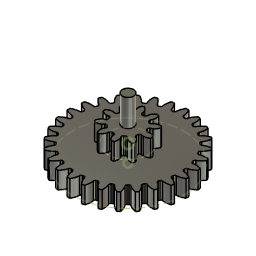
filament-respooler (Autodesk Fusion 360 archive; units mm, degrees)
design "Black Gear (new)"
description: Spur Gear; Module: 2.800000; Num Teeth: 10; Pressure Angle: 20.000000; Backlash: 0.00 mm
description: Spur Gear; Module: 2.800000; Num Teeth: 28; Pressure Angle: 20.000000; Backlash: 0.00 mm
Autodesk Fusion 360 part; units mm, degrees
(part 1 of 11)
sketch "Sketch1" plane through (0, 0, 0) normal (0, 0, 1) x (1, 0, 0) in component "Spur Gear (10 teeth)"
  circle A0 centre (0, 0) radius 10.5892
extrude "Extrude1" add sketch "Sketch1" along normal blind 12 makes body 1 in component "Spur Gear (10 teeth)"
sketch "Sketch2" plane through (0, 0, 0) normal (0, 0, 1) x (1, 0, 0) in component "Spur Gear (10 teeth)"
  spline S0 degree 5 poles (12.9616, -2.2514) (12.9724, -2.2533) (12.9939, -2.2566) (13.0264, -2.2606) (13.0698, -2.2637) (13.1245, -2.2647) (13.1793, -2.2636) (13.2343, -2.2613) (13.2894, -2.2583) (13.3446, -2.2548) (13.3998, -2.2507) (13.4551, -2.246) (13.5104, -2.2404) (13.5658, -2.2337) (13.6212, -2.226) (13.6767, -2.2173) (13.7323, -2.2079) (13.7878, -2.1977) (13.8434, -2.187) (13.899, -2.1756) (13.9546, -2.1637) (14.0101, -2.1511) (14.0657, -2.138) (14.1213, -2.1241) (14.1769, -2.1096) (14.2325, -2.0944) (14.2881, -2.0787) (14.3436, -2.0624) (14.3991, -2.0455) (14.4546, -2.0281) (14.5101, -2.0101) (14.5655, -1.9917) (14.6209, -1.9726) (14.6763, -1.953) (14.7316, -1.9329) (14.7869, -1.9123) (14.8421, -1.8911) (14.8973, -1.8695) (14.9524, -1.8473) (15.0075, -1.8247) (15.0626, -1.8015) (15.1175, -1.7779) (15.1724, -1.7538) (15.2273, -1.7292) (15.282, -1.7041) (15.3368, -1.6785) (15.3914, -1.6525) (15.446, -1.626) (15.5004, -1.5991) (15.5548, -1.5717) (15.6092, -1.5439) (15.6634, -1.5156) (15.7176, -1.4868) (15.7717, -1.4576) (15.8256, -1.428) (15.8795, -1.3979) (15.9333, -1.3674) (15.9871, -1.3365) (16.0407, -1.3051) (16.0942, -1.2733) (16.1476, -1.2411) (16.2009, -1.2085) (16.2541, -1.1755) (16.3072, -1.142) (16.3602, -1.1081) (16.413, -1.0738) (16.4658, -1.0391) (16.5184, -1.004) (16.571, -0.9685) (16.6234, -0.9327) (16.6757, -0.8964) (16.7174, -0.867) (16.7486, -0.8448) (16.7695, -0.8299) (16.7799, -0.8225) knots 0 0 0 0 0 0 0.01428571 0.02857143 0.04285714 0.05714286 0.07142857 0.08571429 0.1 0.11428571 0.12857143 0.14285714 0.15714286 0.17142857 0.18571429 0.2 0.21428571 0.22857143 0.24285714 0.25714286 0.27142857 0.28571429 0.3 0.31428571 0.32857143 0.34285714 0.35714286 0.37142857 0.38571429 0.4 0.41428571 0.42857143 0.44285714 0.45714286 0.47142857 0.48571429 0.5 0.51428571 0.52857143 0.54285714 0.55714286 0.57142857 0.58571429 0.6 0.61428571 0.62857143 0.64285714 0.65714286 0.67142857 0.68571429 0.7 0.71428571 0.72857143 0.74285714 0.75714286 0.77142857 0.78571429 0.8 0.81428571 0.82857143 0.84285714 0.85714286 0.87142857 0.88571429 0.9 0.91428571 0.92857143 0.94285714 0.95714286 0.97142857 0.98571429 1 1 1 1 1 1
  spline S1 degree 5 poles (12.9616, 2.2514) (12.9724, 2.2533) (12.9939, 2.2566) (13.0264, 2.2606) (13.0698, 2.2637) (13.1245, 2.2647) (13.1793, 2.2636) (13.2343, 2.2613) (13.2894, 2.2583) (13.3446, 2.2548) (13.3998, 2.2507) (13.4551, 2.246) (13.5104, 2.2404) (13.5658, 2.2337) (13.6212, 2.226) (13.6767, 2.2173) (13.7323, 2.2079) (13.7878, 2.1977) (13.8434, 2.187) (13.899, 2.1756) (13.9546, 2.1637) (14.0101, 2.1511) (14.0657, 2.138) (14.1213, 2.1241) (14.1769, 2.1096) (14.2325, 2.0944) (14.2881, 2.0787) (14.3436, 2.0624) (14.3991, 2.0455) (14.4546, 2.0281) (14.5101, 2.0101) (14.5655, 1.9917) (14.6209, 1.9726) (14.6763, 1.953) (14.7316, 1.9329) (14.7869, 1.9123) (14.8421, 1.8911) (14.8973, 1.8695) (14.9524, 1.8473) (15.0075, 1.8247) (15.0626, 1.8015) (15.1175, 1.7779) (15.1724, 1.7538) (15.2273, 1.7292) (15.282, 1.7041) (15.3368, 1.6785) (15.3914, 1.6525) (15.446, 1.626) (15.5004, 1.5991) (15.5548, 1.5717) (15.6092, 1.5439) (15.6634, 1.5156) (15.7176, 1.4868) (15.7717, 1.4576) (15.8256, 1.428) (15.8795, 1.3979) (15.9333, 1.3674) (15.9871, 1.3365) (16.0407, 1.3051) (16.0942, 1.2733) (16.1476, 1.2411) (16.2009, 1.2085) (16.2541, 1.1755) (16.3072, 1.142) (16.3602, 1.1081) (16.413, 1.0738) (16.4658, 1.0391) (16.5184, 1.004) (16.571, 0.9685) (16.6234, 0.9327) (16.6757, 0.8964) (16.7174, 0.867) (16.7486, 0.8448) (16.7695, 0.8299) (16.7799, 0.8225) knots 0 0 0 0 0 0 0.01428571 0.02857143 0.04285714 0.05714286 0.07142857 0.08571429 0.1 0.11428571 0.12857143 0.14285714 0.15714286 0.17142857 0.18571429 0.2 0.21428571 0.22857143 0.24285714 0.25714286 0.27142857 0.28571429 0.3 0.31428571 0.32857143 0.34285714 0.35714286 0.37142857 0.38571429 0.4 0.41428571 0.42857143 0.44285714 0.45714286 0.47142857 0.48571429 0.5 0.51428571 0.52857143 0.54285714 0.55714286 0.57142857 0.58571429 0.6 0.61428571 0.62857143 0.64285714 0.65714286 0.67142857 0.68571429 0.7 0.71428571 0.72857143 0.74285714 0.75714286 0.77142857 0.78571429 0.8 0.81428571 0.82857143 0.84285714 0.85714286 0.87142857 0.88571429 0.9 0.91428571 0.92857143 0.94285714 0.95714286 0.97142857 0.98571429 1 1 1 1 1 1
  arc A0 (16.7799, -0.8225) -> (16.7799, 0.8225) centre (0, 0) ccw
  line L0 (10.4231, -1.8122) -> (12.9616, -2.2514)
  line L1 (10.4231, 1.8122) -> (12.9616, 2.2514)
  line L2 (10.4231, -1.8122) -> (10.4231, 1.8122)
  point P0 (13.224, -2.2616)
  point P1 (13.4913, -2.2422)
  point P2 (13.7615, -2.2025)
  point P3 (14.0339, -2.1454)
  point P4 (14.3079, -2.0728)
  point P5 (14.583, -1.9856)
  point P6 (14.8588, -1.8845)
  point P7 (15.135, -1.7701)
  point P8 (15.4111, -1.6429)
  point P9 (15.6869, -1.503)
  point P10 (15.962, -1.3508)
  point P11 (16.2361, -1.1866)
  point P12 (16.5088, -1.0104)
  point P13 (13.224, 2.2616)
  point P14 (13.4913, 2.2422)
  point P15 (13.7615, 2.2025)
  point P16 (14.0339, 2.1454)
  point P17 (14.3079, 2.0728)
  point P18 (14.583, 1.9856)
  point P19 (14.8588, 1.8845)
  point P20 (15.135, 1.7701)
  point P21 (15.4111, 1.6429)
  point P22 (15.6869, 1.503)
  point P23 (15.962, 1.3508)
  point P24 (16.2361, 1.1866)
  point P25 (16.5088, 1.0104)
extrude "Extrude2" add sketch "Sketch2" along normal blind 12 bodies 1 in component "Spur Gear (10 teeth)"
fillet "Fillet1" radius 1 2 edges at (10.4327, -1.8139, 6) (10.4327, 1.8139, 6) on bodies 1 in component "Spur Gear (10 teeth)"
pattern_circular "C-Pattern1" count 10 over 360 about axis through (0, 0, 0) along (0, 0, 1) of "Extrude2", "Fillet1" in component "Spur Gear (10 teeth)"
sketch "Sketch3" plane through (0, 0, 0) normal (0, 0, 1) x (1, 0, 0) in component "Spur Gear (10 teeth)"
  circle A0 centre (0, 0) radius 14 construction
sketch "Sketch1 (2)" plane through (0, 0, 0) normal (0, 0, 1) x (1, 0, 0) in component "Spur Gear (28 teeth)"
  circle A0 centre (0, 0) radius 35.7892
extrude "Extrude1'" add sketch "Sketch1 (2)" along normal blind 12 separate body makes body 2 in component "Spur Gear (28 teeth)"
sketch "Sketch2 (2)" plane through (0, 0, 0) normal (0, 0, 1) x (1, 0, 0) in component "Spur Gear (28 teeth)"
  spline S0 degree 5 poles (36.7431, -2.6133) (36.7583, -2.6144) (36.7885, -2.6161) (36.8339, -2.6177) (36.8945, -2.6178) (36.9702, -2.615) (37.0461, -2.6101) (37.1219, -2.6041) (37.1978, -2.5973) (37.2736, -2.59) (37.3495, -2.5823) (37.4254, -2.5739) (37.5013, -2.5647) (37.5772, -2.5545) (37.6531, -2.5433) (37.7289, -2.5312) (37.8048, -2.5183) (37.8806, -2.5048) (37.9564, -2.4907) (38.0322, -2.476) (38.108, -2.4608) (38.1838, -2.4451) (38.2595, -2.4287) (38.3352, -2.4118) (38.4109, -2.3942) (38.4865, -2.3761) (38.5621, -2.3574) (38.6377, -2.3382) (38.7132, -2.3184) (38.7887, -2.2982) (38.8642, -2.2775) (38.9396, -2.2563) (39.015, -2.2346) (39.0904, -2.2125) (39.1657, -2.1898) (39.2409, -2.1667) (39.3162, -2.1431) (39.3913, -2.1191) (39.4665, -2.0946) (39.5415, -2.0697) (39.6166, -2.0443) (39.6916, -2.0185) (39.7665, -1.9923) (39.8414, -1.9656) (39.9162, -1.9385) (39.991, -1.911) (40.0658, -1.8831) (40.1405, -1.8548) (40.2151, -1.8261) (40.2896, -1.797) (40.3642, -1.7675) (40.4386, -1.7375) (40.513, -1.7072) (40.5874, -1.6765) (40.6616, -1.6455) (40.7359, -1.614) (40.81, -1.5822) (40.8841, -1.55) (40.9581, -1.5174) (41.0321, -1.4844) (41.106, -1.4511) (41.1798, -1.4174) (41.2536, -1.3834) (41.3273, -1.349) (41.401, -1.3142) (41.4745, -1.2791) (41.548, -1.2436) (41.6215, -1.2078) (41.6948, -1.1716) (41.7681, -1.1351) (41.8413, -1.0982) (41.8998, -1.0684) (41.9437, -1.0459) (41.9729, -1.0309) (41.9875, -1.0233) knots 0 0 0 0 0 0 0.01428571 0.02857143 0.04285714 0.05714286 0.07142857 0.08571429 0.1 0.11428571 0.12857143 0.14285714 0.15714286 0.17142857 0.18571429 0.2 0.21428571 0.22857143 0.24285714 0.25714286 0.27142857 0.28571429 0.3 0.31428571 0.32857143 0.34285714 0.35714286 0.37142857 0.38571429 0.4 0.41428571 0.42857143 0.44285714 0.45714286 0.47142857 0.48571429 0.5 0.51428571 0.52857143 0.54285714 0.55714286 0.57142857 0.58571429 0.6 0.61428571 0.62857143 0.64285714 0.65714286 0.67142857 0.68571429 0.7 0.71428571 0.72857143 0.74285714 0.75714286 0.77142857 0.78571429 0.8 0.81428571 0.82857143 0.84285714 0.85714286 0.87142857 0.88571429 0.9 0.91428571 0.92857143 0.94285714 0.95714286 0.97142857 0.98571429 1 1 1 1 1 1
  spline S1 degree 5 poles (36.7431, 2.6133) (36.7583, 2.6144) (36.7885, 2.6161) (36.8339, 2.6177) (36.8945, 2.6178) (36.9702, 2.615) (37.0461, 2.6101) (37.1219, 2.6041) (37.1978, 2.5973) (37.2736, 2.59) (37.3495, 2.5823) (37.4254, 2.5739) (37.5013, 2.5647) (37.5772, 2.5545) (37.6531, 2.5433) (37.7289, 2.5312) (37.8048, 2.5183) (37.8806, 2.5048) (37.9564, 2.4907) (38.0322, 2.476) (38.108, 2.4608) (38.1838, 2.4451) (38.2595, 2.4287) (38.3352, 2.4118) (38.4109, 2.3942) (38.4865, 2.3761) (38.5621, 2.3574) (38.6377, 2.3382) (38.7132, 2.3184) (38.7887, 2.2982) (38.8642, 2.2775) (38.9396, 2.2563) (39.015, 2.2346) (39.0904, 2.2125) (39.1657, 2.1898) (39.2409, 2.1667) (39.3162, 2.1431) (39.3913, 2.1191) (39.4665, 2.0946) (39.5415, 2.0697) (39.6166, 2.0443) (39.6916, 2.0185) (39.7665, 1.9923) (39.8414, 1.9656) (39.9162, 1.9385) (39.991, 1.911) (40.0658, 1.8831) (40.1405, 1.8548) (40.2151, 1.8261) (40.2896, 1.797) (40.3642, 1.7675) (40.4386, 1.7375) (40.513, 1.7072) (40.5874, 1.6765) (40.6616, 1.6455) (40.7359, 1.614) (40.81, 1.5822) (40.8841, 1.55) (40.9581, 1.5174) (41.0321, 1.4844) (41.106, 1.4511) (41.1798, 1.4174) (41.2536, 1.3834) (41.3273, 1.349) (41.401, 1.3142) (41.4745, 1.2791) (41.548, 1.2436) (41.6215, 1.2078) (41.6948, 1.1716) (41.7681, 1.1351) (41.8413, 1.0982) (41.8998, 1.0684) (41.9437, 1.0459) (41.9729, 1.0309) (41.9875, 1.0233) knots 0 0 0 0 0 0 0.01428571 0.02857143 0.04285714 0.05714286 0.07142857 0.08571429 0.1 0.11428571 0.12857143 0.14285714 0.15714286 0.17142857 0.18571429 0.2 0.21428571 0.22857143 0.24285714 0.25714286 0.27142857 0.28571429 0.3 0.31428571 0.32857143 0.34285714 0.35714286 0.37142857 0.38571429 0.4 0.41428571 0.42857143 0.44285714 0.45714286 0.47142857 0.48571429 0.5 0.51428571 0.52857143 0.54285714 0.55714286 0.57142857 0.58571429 0.6 0.61428571 0.62857143 0.64285714 0.65714286 0.67142857 0.68571429 0.7 0.71428571 0.72857143 0.74285714 0.75714286 0.77142857 0.78571429 0.8 0.81428571 0.82857143 0.84285714 0.85714286 0.87142857 0.88571429 0.9 0.91428571 0.92857143 0.94285714 0.95714286 0.97142857 0.98571429 1 1 1 1 1 1
  arc A0 (41.9875, -1.0233) -> (41.9875, 1.0233) centre (0, 0) ccw
  line L0 (35.689, -2.5391) -> (36.7431, -2.6133)
  line L1 (35.689, 2.5391) -> (36.7431, 2.6133)
  line L2 (35.689, -2.5391) -> (35.689, 2.5391)
  point P0 (37.1135, -2.6046)
  point P1 (37.4859, -2.5664)
  point P2 (37.8595, -2.5085)
  point P3 (38.234, -2.4342)
  point P4 (38.6091, -2.3454)
  point P5 (38.9846, -2.2433)
  point P6 (39.3604, -2.1289)
  point P7 (39.7364, -2.0027)
  point P8 (40.1123, -1.8654)
  point P9 (40.4882, -1.7173)
  point P10 (40.8637, -1.5588)
  point P11 (41.2389, -1.3901)
  point P12 (41.6135, -1.2116)
  point P13 (37.1135, 2.6046)
  point P14 (37.4859, 2.5664)
  point P15 (37.8595, 2.5085)
  point P16 (38.234, 2.4342)
  point P17 (38.6091, 2.3454)
  point P18 (38.9846, 2.2433)
  point P19 (39.3604, 2.1289)
  point P20 (39.7364, 2.0027)
  point P21 (40.1123, 1.8654)
  point P22 (40.4882, 1.7173)
  point P23 (40.8637, 1.5588)
  point P24 (41.2389, 1.3901)
  point P25 (41.6135, 1.2116)
extrude "Extrude2'" add sketch "Sketch2 (2)" along normal blind 12 bodies 2 in component "Spur Gear (28 teeth)"
fillet "Fillet1'" radius 1 2 edges at (35.699, -2.5397, 6) (35.699, 2.5397, 6) on bodies 2 in component "Spur Gear (28 teeth)"
pattern_circular "C-Pattern1'" count 28 over 360 about axis through (0, 0, 0) along (0, 0, 1) of "Extrude2'", "Fillet1'" in component "Spur Gear (28 teeth)"
sketch "Sketch3 (2)" plane through (0, 0, 0) normal (0, 0, 1) x (1, 0, 0) in component "Spur Gear (28 teeth)"
  circle A0 centre (0, 0) radius 39.2 construction
sketch "Sketch1 (3)" plane through (0, 0, 12) normal (0, 0, 1) x (-1, 0, 0)
  arc A0 (-9.8732, 3.8277) -> (-10.2374, 2.7066) centre (0, 0) ccw
  arc A1 (-11.3747, 1.9769) -> (-10.2374, 2.7066) centre (-11.2042, 2.9622) ccw
  line L0 (-11.3747, 1.9769) -> (-12.9616, 2.2514)
  spline S0 degree 5 poles (-12.9616, 2.2514) (-12.9724, 2.2533) (-12.9939, 2.2566) (-13.0264, 2.2606) (-13.0698, 2.2637) (-13.1245, 2.2647) (-13.1793, 2.2636) (-13.2343, 2.2613) (-13.2894, 2.2583) (-13.3446, 2.2548) (-13.3998, 2.2507) (-13.4551, 2.246) (-13.5104, 2.2404) (-13.5658, 2.2337) (-13.6212, 2.226) (-13.6767, 2.2173) (-13.7323, 2.2079) (-13.7878, 2.1977) (-13.8434, 2.187) (-13.899, 2.1756) (-13.9546, 2.1637) (-14.0101, 2.1511) (-14.0657, 2.138) (-14.1213, 2.1241) (-14.1769, 2.1096) (-14.2325, 2.0944) (-14.2881, 2.0787) (-14.3436, 2.0624) (-14.3991, 2.0455) (-14.4546, 2.0281) (-14.5101, 2.0101) (-14.5655, 1.9917) (-14.6209, 1.9726) (-14.6763, 1.953) (-14.7316, 1.9329) (-14.7869, 1.9123) (-14.8421, 1.8911) (-14.8973, 1.8695) (-14.9524, 1.8473) (-15.0075, 1.8247) (-15.0626, 1.8015) (-15.1175, 1.7779) (-15.1724, 1.7538) (-15.2273, 1.7292) (-15.282, 1.7041) (-15.3368, 1.6785) (-15.3914, 1.6525) (-15.446, 1.626) (-15.5004, 1.5991) (-15.5548, 1.5717) (-15.6092, 1.5439) (-15.6634, 1.5156) (-15.7176, 1.4868) (-15.7717, 1.4576) (-15.8256, 1.428) (-15.8795, 1.3979) (-15.9333, 1.3674) (-15.9871, 1.3365) (-16.0407, 1.3051) (-16.0942, 1.2733) (-16.1476, 1.2411) (-16.2009, 1.2085) (-16.2541, 1.1755) (-16.3072, 1.142) (-16.3602, 1.1081) (-16.413, 1.0738) (-16.4658, 1.0391) (-16.5184, 1.004) (-16.571, 0.9685) (-16.6234, 0.9327) (-16.6757, 0.8964) (-16.7174, 0.867) (-16.7486, 0.8448) (-16.7695, 0.8299) (-16.7799, 0.8225) knots 0 0 0 0 0 0 0.01428571 0.02857143 0.04285714 0.05714286 0.07142857 0.08571429 0.1 0.11428571 0.12857143 0.14285714 0.15714286 0.17142857 0.18571429 0.2 0.21428571 0.22857143 0.24285714 0.25714286 0.27142857 0.28571429 0.3 0.31428571 0.32857143 0.34285714 0.35714286 0.37142857 0.38571429 0.4 0.41428571 0.42857143 0.44285714 0.45714286 0.47142857 0.48571429 0.5 0.51428571 0.52857143 0.54285714 0.55714286 0.57142857 0.58571429 0.6 0.61428571 0.62857143 0.64285714 0.65714286 0.67142857 0.68571429 0.7 0.71428571 0.72857143 0.74285714 0.75714286 0.77142857 0.78571429 0.8 0.81428571 0.82857143 0.84285714 0.85714286 0.87142857 0.88571429 0.9 0.91428571 0.92857143 0.94285714 0.95714286 0.97142857 0.98571429 1 1 1 1 1 1
  arc A2 (-16.7799, 0.8225) -> (-16.7799, -0.8225) centre (0, 0) ccw
  spline S1 degree 5 poles (-16.7799, -0.8225) (-16.7695, -0.8299) (-16.7486, -0.8448) (-16.7174, -0.867) (-16.6757, -0.8964) (-16.6234, -0.9327) (-16.571, -0.9685) (-16.5184, -1.004) (-16.4658, -1.0391) (-16.413, -1.0738) (-16.3602, -1.1081) (-16.3072, -1.142) (-16.2541, -1.1755) (-16.2009, -1.2085) (-16.1476, -1.2411) (-16.0942, -1.2733) (-16.0407, -1.3051) (-15.9871, -1.3365) (-15.9333, -1.3674) (-15.8795, -1.3979) (-15.8256, -1.428) (-15.7717, -1.4576) (-15.7176, -1.4868) (-15.6634, -1.5156) (-15.6092, -1.5439) (-15.5548, -1.5717) (-15.5004, -1.5991) (-15.446, -1.626) (-15.3914, -1.6525) (-15.3368, -1.6785) (-15.282, -1.7041) (-15.2273, -1.7292) (-15.1724, -1.7538) (-15.1175, -1.7779) (-15.0626, -1.8015) (-15.0075, -1.8247) (-14.9524, -1.8473) (-14.8973, -1.8695) (-14.8421, -1.8911) (-14.7869, -1.9123) (-14.7316, -1.9329) (-14.6763, -1.953) (-14.6209, -1.9726) (-14.5655, -1.9917) (-14.5101, -2.0101) (-14.4546, -2.0281) (-14.3991, -2.0455) (-14.3436, -2.0624) (-14.2881, -2.0787) (-14.2325, -2.0944) (-14.1769, -2.1096) (-14.1213, -2.1241) (-14.0657, -2.138) (-14.0101, -2.1511) (-13.9546, -2.1637) (-13.899, -2.1756) (-13.8434, -2.187) (-13.7878, -2.1977) (-13.7323, -2.2079) (-13.6767, -2.2173) (-13.6212, -2.226) (-13.5658, -2.2337) (-13.5104, -2.2404) (-13.4551, -2.246) (-13.3998, -2.2507) (-13.3446, -2.2548) (-13.2894, -2.2583) (-13.2343, -2.2613) (-13.1793, -2.2636) (-13.1245, -2.2647) (-13.0698, -2.2637) (-13.0264, -2.2606) (-12.9939, -2.2566) (-12.9724, -2.2533) (-12.9616, -2.2514) knots -1 -1 -1 -1 -1 -1 -0.98571429 -0.97142857 -0.95714286 -0.94285714 -0.92857143 -0.91428571 -0.9 -0.88571429 -0.87142857 -0.85714286 -0.84285714 -0.82857143 -0.81428571 -0.8 -0.78571429 -0.77142857 -0.75714286 -0.74285714 -0.72857143 -0.71428571 -0.7 -0.68571429 -0.67142857 -0.65714286 -0.64285714 -0.62857143 -0.61428571 -0.6 -0.58571429 -0.57142857 -0.55714286 -0.54285714 -0.52857143 -0.51428571 -0.5 -0.48571429 -0.47142857 -0.45714286 -0.44285714 -0.42857143 -0.41428571 -0.4 -0.38571429 -0.37142857 -0.35714286 -0.34285714 -0.32857143 -0.31428571 -0.3 -0.28571429 -0.27142857 -0.25714286 -0.24285714 -0.22857143 -0.21428571 -0.2 -0.18571429 -0.17142857 -0.15714286 -0.14285714 -0.12857143 -0.11428571 -0.1 -0.08571429 -0.07142857 -0.05714286 -0.04285714 -0.02857143 -0.01428571 0 0 0 0 0 0
  line L1 (-12.9616, -2.2514) -> (-11.3747, -1.9769)
  arc A3 (-10.2374, -2.7066) -> (-11.3747, -1.9769) centre (-11.2042, -2.9622) ccw
  arc A4 (-10.2374, -2.7066) -> (-9.8732, -3.8277) centre (0, 0) ccw
  arc A5 (-10.3643, -5.0866) -> (-9.8732, -3.8277) centre (-10.8056, -4.1892) ccw
  line L2 (-10.3643, -5.0866) -> (-11.8095, -5.7972)
  spline S2 degree 5 poles (-11.8095, -5.7972) (-11.8193, -5.802) (-11.8387, -5.812) (-11.8673, -5.8279) (-11.9043, -5.8509) (-11.9491, -5.8822) (-11.9928, -5.9153) (-12.036, -5.9495) (-12.0788, -5.9844) (-12.1213, -6.0196) (-12.1636, -6.0553) (-12.2055, -6.0916) (-12.247, -6.1287) (-12.2879, -6.1667) (-12.3282, -6.2055) (-12.368, -6.2451) (-12.4074, -6.2854) (-12.4464, -6.3263) (-12.485, -6.3677) (-12.5233, -6.4095) (-12.5613, -6.4518) (-12.5989, -6.4946) (-12.6361, -6.538) (-12.6729, -6.5819) (-12.7093, -6.6263) (-12.7454, -6.6712) (-12.7811, -6.7166) (-12.8164, -6.7625) (-12.8515, -6.8087) (-12.8861, -6.8554) (-12.9204, -6.9026) (-12.9544, -6.9501) (-12.988, -6.9981) (-13.0213, -7.0465) (-13.0543, -7.0952) (-13.0869, -7.1444) (-13.1191, -7.194) (-13.151, -7.244) (-13.1826, -7.2943) (-13.2139, -7.345) (-13.2448, -7.3961) (-13.2753, -7.4475) (-13.3056, -7.4993) (-13.3355, -7.5514) (-13.3651, -7.6039) (-13.3943, -7.6568) (-13.4232, -7.7099) (-13.4518, -7.7634) (-13.48, -7.8172) (-13.508, -7.8714) (-13.5355, -7.9258) (-13.5628, -7.9806) (-13.5897, -8.0357) (-13.6163, -8.0911) (-13.6426, -8.1468) (-13.6685, -8.2028) (-13.6941, -8.2591) (-13.7194, -8.3157) (-13.7443, -8.3726) (-13.7689, -8.4298) (-13.7932, -8.4872) (-13.8171, -8.5449) (-13.8407, -8.603) (-13.864, -8.6612) (-13.887, -8.7198) (-13.9096, -8.7786) (-13.9319, -8.8377) (-13.9539, -8.897) (-13.9755, -8.9566) (-13.9968, -9.0164) (-14.0178, -9.0765) (-14.0343, -9.1248) (-14.0465, -9.1611) (-14.0546, -9.1854) (-14.0586, -9.1976) knots 0 0 0 0 0 0 0.01428571 0.02857143 0.04285714 0.05714286 0.07142857 0.08571429 0.1 0.11428571 0.12857143 0.14285714 0.15714286 0.17142857 0.18571429 0.2 0.21428571 0.22857143 0.24285714 0.25714286 0.27142857 0.28571429 0.3 0.31428571 0.32857143 0.34285714 0.35714286 0.37142857 0.38571429 0.4 0.41428571 0.42857143 0.44285714 0.45714286 0.47142857 0.48571429 0.5 0.51428571 0.52857143 0.54285714 0.55714286 0.57142857 0.58571429 0.6 0.61428571 0.62857143 0.64285714 0.65714286 0.67142857 0.68571429 0.7 0.71428571 0.72857143 0.74285714 0.75714286 0.77142857 0.78571429 0.8 0.81428571 0.82857143 0.84285714 0.85714286 0.87142857 0.88571429 0.9 0.91428571 0.92857143 0.94285714 0.95714286 0.97142857 0.98571429 1 1 1 1 1 1
  arc A6 (-14.0586, -9.1976) -> (-13.0918, -10.5283) centre (0, 0) ccw
  spline S3 degree 5 poles (-13.0918, -10.5283) (-13.079, -10.5283) (-13.0534, -10.5281) (-13.0151, -10.5277) (-12.964, -10.5269) (-12.9004, -10.5255) (-12.8369, -10.5237) (-12.7735, -10.5216) (-12.7103, -10.519) (-12.6472, -10.5161) (-12.5843, -10.5128) (-12.5215, -10.509) (-12.4589, -10.5049) (-12.3965, -10.5003) (-12.3341, -10.4954) (-12.272, -10.4901) (-12.21, -10.4843) (-12.1482, -10.4782) (-12.0866, -10.4716) (-12.0251, -10.4647) (-11.9639, -10.4573) (-11.9028, -10.4496) (-11.8419, -10.4414) (-11.7812, -10.4328) (-11.7206, -10.4238) (-11.6603, -10.4144) (-11.6002, -10.4046) (-11.5403, -10.3944) (-11.4806, -10.3837) (-11.4211, -10.3727) (-11.3618, -10.3612) (-11.3027, -10.3493) (-11.2439, -10.337) (-11.1853, -10.3242) (-11.127, -10.311) (-11.0688, -10.2974) (-11.011, -10.2833) (-10.9533, -10.2689) (-10.8959, -10.2539) (-10.8388, -10.2386) (-10.782, -10.2228) (-10.7254, -10.2065) (-10.6691, -10.1898) (-10.6131, -10.1727) (-10.5574, -10.1551) (-10.5019, -10.137) (-10.4468, -10.1184) (-10.392, -10.0994) (-10.3375, -10.08) (-10.2833, -10.0601) (-10.2294, -10.0397) (-10.1759, -10.0187) (-10.1228, -9.9973) (-10.07, -9.9753) (-10.0177, -9.9528) (-9.9657, -9.9297) (-9.9141, -9.9062) (-9.8628, -9.8823) (-9.8119, -9.8578) (-9.7614, -9.8328) (-9.7114, -9.8072) (-9.662, -9.7809) (-9.6133, -9.7537) (-9.5652, -9.7257) (-9.5177, -9.6971) (-9.4707, -9.6679) (-9.424, -9.6383) (-9.3777, -9.6084) (-9.3318, -9.5779) (-9.2868, -9.5465) (-9.2432, -9.5136) (-9.2098, -9.4855) (-9.1859, -9.4633) (-9.1704, -9.4479) (-9.1628, -9.4401) knots -1 -1 -1 -1 -1 -1 -0.98571429 -0.97142857 -0.95714286 -0.94285714 -0.92857143 -0.91428571 -0.9 -0.88571429 -0.87142857 -0.85714286 -0.84285714 -0.82857143 -0.81428571 -0.8 -0.78571429 -0.77142857 -0.75714286 -0.74285714 -0.72857143 -0.71428571 -0.7 -0.68571429 -0.67142857 -0.65714286 -0.64285714 -0.62857143 -0.61428571 -0.6 -0.58571429 -0.57142857 -0.55714286 -0.54285714 -0.52857143 -0.51428571 -0.5 -0.48571429 -0.47142857 -0.45714286 -0.44285714 -0.42857143 -0.41428571 -0.4 -0.38571429 -0.37142857 -0.35714286 -0.34285714 -0.32857143 -0.31428571 -0.3 -0.28571429 -0.27142857 -0.25714286 -0.24285714 -0.22857143 -0.21428571 -0.2 -0.18571429 -0.17142857 -0.15714286 -0.14285714 -0.12857143 -0.11428571 -0.1 -0.08571429 -0.07142857 -0.05714286 -0.04285714 -0.02857143 -0.01428571 0 0 0 0 0 0
  line L3 (-9.1628, -9.4401) -> (-8.0404, -8.2852)
  arc A7 (-6.6914, -8.2071) -> (-8.0404, -8.2852) centre (-7.3233, -8.9822) ccw
  arc A8 (-6.6914, -8.2071) -> (-5.7377, -8.9) centre (0, 0) ccw
  arc A9 (-5.3951, -10.2071) -> (-5.7377, -8.9) centre (-6.2795, -9.7405) ccw
  line L4 (-5.3951, -10.2071) -> (-6.1466, -11.6315)
  spline S4 degree 5 poles (-6.1466, -11.6315) (-6.1517, -11.6412) (-6.1615, -11.6606) (-6.1753, -11.6903) (-6.1917, -11.7307) (-6.2095, -11.7823) (-6.2255, -11.8348) (-6.2402, -11.8878) (-6.2544, -11.9412) (-6.2681, -11.9947) (-6.2813, -12.0484) (-6.2939, -12.1025) (-6.3057, -12.1568) (-6.3164, -12.2116) (-6.3262, -12.2667) (-6.3352, -12.3221) (-6.3433, -12.3779) (-6.3508, -12.4339) (-6.3578, -12.49) (-6.3642, -12.5464) (-6.37, -12.603) (-6.3752, -12.6597) (-6.3799, -12.7167) (-6.3839, -12.7738) (-6.3872, -12.8312) (-6.39, -12.8887) (-6.3922, -12.9464) (-6.3938, -13.0043) (-6.395, -13.0623) (-6.3956, -13.1204) (-6.3956, -13.1787) (-6.3952, -13.2372) (-6.3942, -13.2957) (-6.3927, -13.3545) (-6.3906, -13.4133) (-6.3881, -13.4722) (-6.385, -13.5313) (-6.3815, -13.5905) (-6.3775, -13.6498) (-6.3729, -13.7092) (-6.3679, -13.7686) (-6.3624, -13.8282) (-6.3565, -13.8879) (-6.35, -13.9477) (-6.3431, -14.0075) (-6.3357, -14.0674) (-6.3278, -14.1274) (-6.3195, -14.1875) (-6.3107, -14.2476) (-6.3015, -14.3079) (-6.2918, -14.3681) (-6.2816, -14.4285) (-6.271, -14.4889) (-6.26, -14.5493) (-6.2485, -14.6098) (-6.2365, -14.6704) (-6.2242, -14.731) (-6.2113, -14.7916) (-6.1981, -14.8523) (-6.1844, -14.913) (-6.1703, -14.9737) (-6.1557, -15.0345) (-6.1407, -15.0953) (-6.1253, -15.1562) (-6.1095, -15.217) (-6.0932, -15.2779) (-6.0765, -15.3388) (-6.0594, -15.3997) (-6.0419, -15.4606) (-6.0239, -15.5216) (-6.0055, -15.5825) (-5.9905, -15.6313) (-5.9791, -15.6679) (-5.9714, -15.6922) (-5.9675, -15.7044) knots 0 0 0 0 0 0 0.01428571 0.02857143 0.04285714 0.05714286 0.07142857 0.08571429 0.1 0.11428571 0.12857143 0.14285714 0.15714286 0.17142857 0.18571429 0.2 0.21428571 0.22857143 0.24285714 0.25714286 0.27142857 0.28571429 0.3 0.31428571 0.32857143 0.34285714 0.35714286 0.37142857 0.38571429 0.4 0.41428571 0.42857143 0.44285714 0.45714286 0.47142857 0.48571429 0.5 0.51428571 0.52857143 0.54285714 0.55714286 0.57142857 0.58571429 0.6 0.61428571 0.62857143 0.64285714 0.65714286 0.67142857 0.68571429 0.7 0.71428571 0.72857143 0.74285714 0.75714286 0.77142857 0.78571429 0.8 0.81428571 0.82857143 0.84285714 0.85714286 0.87142857 0.88571429 0.9 0.91428571 0.92857143 0.94285714 0.95714286 0.97142857 0.98571429 1 1 1 1 1 1
  arc A10 (-5.9675, -15.7044) -> (-4.403, -16.2127) centre (0, 0) ccw
  spline S5 degree 5 poles (-4.403, -16.2127) (-4.3927, -16.2052) (-4.3722, -16.19) (-4.3414, -16.1671) (-4.3006, -16.1365) (-4.2499, -16.098) (-4.1996, -16.0592) (-4.1496, -16.0202) (-4.0999, -15.981) (-4.0506, -15.9416) (-4.0017, -15.9019) (-3.9531, -15.8619) (-3.9049, -15.8218) (-3.857, -15.7814) (-3.8095, -15.7408) (-3.7624, -15.7) (-3.7156, -15.6589) (-3.6692, -15.6176) (-3.6232, -15.5761) (-3.5775, -15.5343) (-3.5323, -15.4924) (-3.4874, -15.4502) (-3.443, -15.4078) (-3.3989, -15.3651) (-3.3552, -15.3223) (-3.3119, -15.2792) (-3.2691, -15.2359) (-3.2266, -15.1924) (-3.1846, -15.1487) (-3.1429, -15.1048) (-3.1017, -15.0607) (-3.061, -15.0163) (-3.0206, -14.9718) (-2.9807, -14.927) (-2.9412, -14.882) (-2.9022, -14.8369) (-2.8637, -14.7915) (-2.8255, -14.7459) (-2.7879, -14.7001) (-2.7507, -14.6541) (-2.714, -14.6079) (-2.6778, -14.5615) (-2.642, -14.5149) (-2.6068, -14.4681) (-2.5721, -14.4211) (-2.5379, -14.3739) (-2.5042, -14.3265) (-2.471, -14.2789) (-2.4383, -14.2311) (-2.4062, -14.1831) (-2.3746, -14.1349) (-2.3436, -14.0866) (-2.3132, -14.038) (-2.2835, -13.9892) (-2.2544, -13.9402) (-2.2259, -13.891) (-2.1979, -13.8417) (-2.1705, -13.7921) (-2.1437, -13.7424) (-2.1175, -13.6925) (-2.0921, -13.6424) (-2.0677, -13.5921) (-2.0442, -13.5415) (-2.0218, -13.4906) (-2.0002, -13.4395) (-1.9793, -13.3882) (-1.9589, -13.3369) (-1.939, -13.2854) (-1.9198, -13.2338) (-1.9019, -13.1819) (-1.8859, -13.1297) (-1.8754, -13.0874) (-1.8691, -13.0553) (-1.8657, -13.0338) (-1.8641, -13.023) knots -1 -1 -1 -1 -1 -1 -0.98571429 -0.97142857 -0.95714286 -0.94285714 -0.92857143 -0.91428571 -0.9 -0.88571429 -0.87142857 -0.85714286 -0.84285714 -0.82857143 -0.81428571 -0.8 -0.78571429 -0.77142857 -0.75714286 -0.74285714 -0.72857143 -0.71428571 -0.7 -0.68571429 -0.67142857 -0.65714286 -0.64285714 -0.62857143 -0.61428571 -0.6 -0.58571429 -0.57142857 -0.55714286 -0.54285714 -0.52857143 -0.51428571 -0.5 -0.48571429 -0.47142857 -0.45714286 -0.44285714 -0.42857143 -0.41428571 -0.4 -0.38571429 -0.37142857 -0.35714286 -0.34285714 -0.32857143 -0.31428571 -0.3 -0.28571429 -0.27142857 -0.25714286 -0.24285714 -0.22857143 -0.21428571 -0.2 -0.18571429 -0.17142857 -0.15714286 -0.14285714 -0.12857143 -0.11428571 -0.1 -0.08571429 -0.07142857 -0.05714286 -0.04285714 -0.02857143 -0.01428571 0 0 0 0 0 0
  line L5 (-1.8641, -13.023) -> (-1.6349, -11.4289)
  arc A11 (-0.5894, -10.5728) -> (-1.6349, -11.4289) centre (-0.6451, -11.5712) ccw
  arc A12 (-0.5894, -10.5728) -> (0.5894, -10.5728) centre (0, 0) ccw
  arc A13 (1.6349, -11.4289) -> (0.5894, -10.5728) centre (0.6451, -11.5712) ccw
  line L6 (1.6349, -11.4289) -> (1.8641, -13.023)
  spline S6 degree 5 poles (1.8641, -13.023) (1.8657, -13.0338) (1.8691, -13.0553) (1.8754, -13.0874) (1.8859, -13.1297) (1.9019, -13.1819) (1.9198, -13.2338) (1.939, -13.2854) (1.9589, -13.3369) (1.9793, -13.3882) (2.0002, -13.4395) (2.0218, -13.4906) (2.0442, -13.5415) (2.0677, -13.5921) (2.0921, -13.6424) (2.1175, -13.6925) (2.1437, -13.7424) (2.1705, -13.7921) (2.1979, -13.8417) (2.2259, -13.891) (2.2544, -13.9402) (2.2835, -13.9892) (2.3132, -14.038) (2.3436, -14.0866) (2.3746, -14.1349) (2.4062, -14.1831) (2.4383, -14.2311) (2.471, -14.2789) (2.5042, -14.3265) (2.5379, -14.3739) (2.5721, -14.4211) (2.6068, -14.4681) (2.642, -14.5149) (2.6778, -14.5615) (2.714, -14.6079) (2.7507, -14.6541) (2.7879, -14.7001) (2.8255, -14.7459) (2.8637, -14.7915) (2.9022, -14.8369) (2.9412, -14.882) (2.9807, -14.927) (3.0206, -14.9718) (3.061, -15.0163) (3.1017, -15.0607) (3.1429, -15.1048) (3.1846, -15.1487) (3.2266, -15.1924) (3.2691, -15.2359) (3.3119, -15.2792) (3.3552, -15.3223) (3.3989, -15.3651) (3.443, -15.4078) (3.4874, -15.4502) (3.5323, -15.4924) (3.5775, -15.5343) (3.6232, -15.5761) (3.6692, -15.6176) (3.7156, -15.6589) (3.7624, -15.7) (3.8095, -15.7408) (3.857, -15.7814) (3.9049, -15.8218) (3.9531, -15.8619) (4.0017, -15.9019) (4.0506, -15.9416) (4.0999, -15.981) (4.1496, -16.0202) (4.1996, -16.0592) (4.2499, -16.098) (4.3006, -16.1365) (4.3414, -16.1671) (4.3722, -16.19) (4.3927, -16.2052) (4.403, -16.2127) knots 0 0 0 0 0 0 0.01428571 0.02857143 0.04285714 0.05714286 0.07142857 0.08571429 0.1 0.11428571 0.12857143 0.14285714 0.15714286 0.17142857 0.18571429 0.2 0.21428571 0.22857143 0.24285714 0.25714286 0.27142857 0.28571429 0.3 0.31428571 0.32857143 0.34285714 0.35714286 0.37142857 0.38571429 0.4 0.41428571 0.42857143 0.44285714 0.45714286 0.47142857 0.48571429 0.5 0.51428571 0.52857143 0.54285714 0.55714286 0.57142857 0.58571429 0.6 0.61428571 0.62857143 0.64285714 0.65714286 0.67142857 0.68571429 0.7 0.71428571 0.72857143 0.74285714 0.75714286 0.77142857 0.78571429 0.8 0.81428571 0.82857143 0.84285714 0.85714286 0.87142857 0.88571429 0.9 0.91428571 0.92857143 0.94285714 0.95714286 0.97142857 0.98571429 1 1 1 1 1 1
  arc A14 (4.403, -16.2127) -> (5.9675, -15.7044) centre (0, 0) ccw
  spline S7 degree 5 poles (5.9675, -15.7044) (5.9714, -15.6922) (5.9791, -15.6679) (5.9905, -15.6313) (6.0055, -15.5825) (6.0239, -15.5216) (6.0419, -15.4606) (6.0594, -15.3997) (6.0765, -15.3388) (6.0932, -15.2779) (6.1095, -15.217) (6.1253, -15.1562) (6.1407, -15.0953) (6.1557, -15.0345) (6.1703, -14.9737) (6.1844, -14.913) (6.1981, -14.8523) (6.2113, -14.7916) (6.2242, -14.731) (6.2365, -14.6704) (6.2485, -14.6098) (6.26, -14.5493) (6.271, -14.4889) (6.2816, -14.4285) (6.2918, -14.3681) (6.3015, -14.3079) (6.3107, -14.2476) (6.3195, -14.1875) (6.3278, -14.1274) (6.3357, -14.0674) (6.3431, -14.0075) (6.35, -13.9477) (6.3565, -13.8879) (6.3624, -13.8282) (6.3679, -13.7686) (6.3729, -13.7092) (6.3775, -13.6498) (6.3815, -13.5905) (6.385, -13.5313) (6.3881, -13.4722) (6.3906, -13.4133) (6.3927, -13.3545) (6.3942, -13.2957) (6.3952, -13.2372) (6.3956, -13.1787) (6.3956, -13.1204) (6.395, -13.0623) (6.3938, -13.0043) (6.3922, -12.9464) (6.39, -12.8887) (6.3872, -12.8312) (6.3839, -12.7738) (6.3799, -12.7167) (6.3752, -12.6597) (6.37, -12.603) (6.3642, -12.5464) (6.3578, -12.49) (6.3508, -12.4339) (6.3433, -12.3779) (6.3352, -12.3221) (6.3262, -12.2667) (6.3164, -12.2116) (6.3057, -12.1568) (6.2939, -12.1025) (6.2813, -12.0484) (6.2681, -11.9947) (6.2544, -11.9412) (6.2402, -11.8878) (6.2255, -11.8348) (6.2095, -11.7823) (6.1917, -11.7307) (6.1753, -11.6903) (6.1615, -11.6606) (6.1517, -11.6412) (6.1466, -11.6315) knots -1 -1 -1 -1 -1 -1 -0.98571429 -0.97142857 -0.95714286 -0.94285714 -0.92857143 -0.91428571 -0.9 -0.88571429 -0.87142857 -0.85714286 -0.84285714 -0.82857143 -0.81428571 -0.8 -0.78571429 -0.77142857 -0.75714286 -0.74285714 -0.72857143 -0.71428571 -0.7 -0.68571429 -0.67142857 -0.65714286 -0.64285714 -0.62857143 -0.61428571 -0.6 -0.58571429 -0.57142857 -0.55714286 -0.54285714 -0.52857143 -0.51428571 -0.5 -0.48571429 -0.47142857 -0.45714286 -0.44285714 -0.42857143 -0.41428571 -0.4 -0.38571429 -0.37142857 -0.35714286 -0.34285714 -0.32857143 -0.31428571 -0.3 -0.28571429 -0.27142857 -0.25714286 -0.24285714 -0.22857143 -0.21428571 -0.2 -0.18571429 -0.17142857 -0.15714286 -0.14285714 -0.12857143 -0.11428571 -0.1 -0.08571429 -0.07142857 -0.05714286 -0.04285714 -0.02857143 -0.01428571 0 0 0 0 0 0
  line L7 (6.1466, -11.6315) -> (5.3951, -10.2071)
  arc A15 (5.7377, -8.9) -> (5.3951, -10.2071) centre (6.2795, -9.7405) ccw
  arc A16 (5.7377, -8.9) -> (6.6914, -8.2071) centre (0, 0) ccw
  arc A17 (8.0404, -8.2852) -> (6.6914, -8.2071) centre (7.3233, -8.9822) ccw
  line L8 (8.0404, -8.2852) -> (9.1628, -9.4401)
  spline S8 degree 5 poles (9.1628, -9.4401) (9.1704, -9.4479) (9.1859, -9.4633) (9.2098, -9.4855) (9.2432, -9.5136) (9.2868, -9.5465) (9.3318, -9.5779) (9.3777, -9.6084) (9.424, -9.6383) (9.4707, -9.6679) (9.5177, -9.6971) (9.5652, -9.7257) (9.6133, -9.7537) (9.662, -9.7809) (9.7114, -9.8072) (9.7614, -9.8328) (9.8119, -9.8578) (9.8628, -9.8823) (9.9141, -9.9062) (9.9657, -9.9297) (10.0177, -9.9528) (10.07, -9.9753) (10.1228, -9.9973) (10.1759, -10.0187) (10.2294, -10.0397) (10.2833, -10.0601) (10.3375, -10.08) (10.392, -10.0994) (10.4468, -10.1184) (10.5019, -10.137) (10.5574, -10.1551) (10.6131, -10.1727) (10.6691, -10.1898) (10.7254, -10.2065) (10.782, -10.2228) (10.8388, -10.2386) (10.8959, -10.2539) (10.9533, -10.2689) (11.011, -10.2833) (11.0688, -10.2974) (11.127, -10.311) (11.1853, -10.3242) (11.2439, -10.337) (11.3027, -10.3493) (11.3618, -10.3612) (11.4211, -10.3727) (11.4806, -10.3837) (11.5403, -10.3944) (11.6002, -10.4046) (11.6603, -10.4144) (11.7206, -10.4238) (11.7812, -10.4328) (11.8419, -10.4414) (11.9028, -10.4496) (11.9639, -10.4573) (12.0251, -10.4647) (12.0866, -10.4716) (12.1482, -10.4782) (12.21, -10.4843) (12.272, -10.4901) (12.3341, -10.4954) (12.3965, -10.5003) (12.4589, -10.5049) (12.5215, -10.509) (12.5843, -10.5128) (12.6472, -10.5161) (12.7103, -10.519) (12.7735, -10.5216) (12.8369, -10.5237) (12.9004, -10.5255) (12.964, -10.5269) (13.0151, -10.5277) (13.0534, -10.5281) (13.079, -10.5283) (13.0918, -10.5283) knots 0 0 0 0 0 0 0.01428571 0.02857143 0.04285714 0.05714286 0.07142857 0.08571429 0.1 0.11428571 0.12857143 0.14285714 0.15714286 0.17142857 0.18571429 0.2 0.21428571 0.22857143 0.24285714 0.25714286 0.27142857 0.28571429 0.3 0.31428571 0.32857143 0.34285714 0.35714286 0.37142857 0.38571429 0.4 0.41428571 0.42857143 0.44285714 0.45714286 0.47142857 0.48571429 0.5 0.51428571 0.52857143 0.54285714 0.55714286 0.57142857 0.58571429 0.6 0.61428571 0.62857143 0.64285714 0.65714286 0.67142857 0.68571429 0.7 0.71428571 0.72857143 0.74285714 0.75714286 0.77142857 0.78571429 0.8 0.81428571 0.82857143 0.84285714 0.85714286 0.87142857 0.88571429 0.9 0.91428571 0.92857143 0.94285714 0.95714286 0.97142857 0.98571429 1 1 1 1 1 1
  arc A18 (13.0918, -10.5283) -> (14.0586, -9.1976) centre (0, 0) ccw
  spline S9 degree 5 poles (14.0586, -9.1976) (14.0546, -9.1854) (14.0465, -9.1611) (14.0343, -9.1248) (14.0178, -9.0765) (13.9968, -9.0164) (13.9755, -8.9566) (13.9539, -8.897) (13.9319, -8.8377) (13.9096, -8.7786) (13.887, -8.7198) (13.864, -8.6612) (13.8407, -8.603) (13.8171, -8.5449) (13.7932, -8.4872) (13.7689, -8.4298) (13.7443, -8.3726) (13.7194, -8.3157) (13.6941, -8.2591) (13.6685, -8.2028) (13.6426, -8.1468) (13.6163, -8.0911) (13.5897, -8.0357) (13.5628, -7.9806) (13.5355, -7.9258) (13.508, -7.8714) (13.48, -7.8172) (13.4518, -7.7634) (13.4232, -7.7099) (13.3943, -7.6568) (13.3651, -7.6039) (13.3355, -7.5514) (13.3056, -7.4993) (13.2753, -7.4475) (13.2448, -7.3961) (13.2139, -7.345) (13.1826, -7.2943) (13.151, -7.244) (13.1191, -7.194) (13.0869, -7.1444) (13.0543, -7.0952) (13.0213, -7.0465) (12.988, -6.9981) (12.9544, -6.9501) (12.9204, -6.9026) (12.8861, -6.8554) (12.8515, -6.8087) (12.8164, -6.7625) (12.7811, -6.7166) (12.7454, -6.6712) (12.7093, -6.6263) (12.6729, -6.5819) (12.6361, -6.538) (12.5989, -6.4946) (12.5613, -6.4518) (12.5233, -6.4095) (12.485, -6.3677) (12.4464, -6.3263) (12.4074, -6.2854) (12.368, -6.2451) (12.3282, -6.2055) (12.2879, -6.1667) (12.247, -6.1287) (12.2055, -6.0916) (12.1636, -6.0553) (12.1213, -6.0196) (12.0788, -5.9844) (12.036, -5.9495) (11.9928, -5.9153) (11.9491, -5.8822) (11.9043, -5.8509) (11.8673, -5.8279) (11.8387, -5.812) (11.8193, -5.802) (11.8095, -5.7972) knots -1 -1 -1 -1 -1 -1 -0.98571429 -0.97142857 -0.95714286 -0.94285714 -0.92857143 -0.91428571 -0.9 -0.88571429 -0.87142857 -0.85714286 -0.84285714 -0.82857143 -0.81428571 -0.8 -0.78571429 -0.77142857 -0.75714286 -0.74285714 -0.72857143 -0.71428571 -0.7 -0.68571429 -0.67142857 -0.65714286 -0.64285714 -0.62857143 -0.61428571 -0.6 -0.58571429 -0.57142857 -0.55714286 -0.54285714 -0.52857143 -0.51428571 -0.5 -0.48571429 -0.47142857 -0.45714286 -0.44285714 -0.42857143 -0.41428571 -0.4 -0.38571429 -0.37142857 -0.35714286 -0.34285714 -0.32857143 -0.31428571 -0.3 -0.28571429 -0.27142857 -0.25714286 -0.24285714 -0.22857143 -0.21428571 -0.2 -0.18571429 -0.17142857 -0.15714286 -0.14285714 -0.12857143 -0.11428571 -0.1 -0.08571429 -0.07142857 -0.05714286 -0.04285714 -0.02857143 -0.01428571 0 0 0 0 0 0
  line L9 (11.8095, -5.7972) -> (10.3643, -5.0866)
  arc A19 (9.8732, -3.8277) -> (10.3643, -5.0866) centre (10.8056, -4.1892) ccw
  arc A20 (9.8732, -3.8277) -> (10.2374, -2.7066) centre (0, 0) ccw
  arc A21 (11.3747, -1.9769) -> (10.2374, -2.7066) centre (11.2042, -2.9622) ccw
  line L10 (11.3747, -1.9769) -> (12.9616, -2.2514)
  spline S10 degree 5 poles (12.9616, -2.2514) (12.9724, -2.2533) (12.9939, -2.2566) (13.0264, -2.2606) (13.0698, -2.2637) (13.1245, -2.2647) (13.1793, -2.2636) (13.2343, -2.2613) (13.2894, -2.2583) (13.3446, -2.2548) (13.3998, -2.2507) (13.4551, -2.246) (13.5104, -2.2404) (13.5658, -2.2337) (13.6212, -2.226) (13.6767, -2.2173) (13.7323, -2.2079) (13.7878, -2.1977) (13.8434, -2.187) (13.899, -2.1756) (13.9546, -2.1637) (14.0101, -2.1511) (14.0657, -2.138) (14.1213, -2.1241) (14.1769, -2.1096) (14.2325, -2.0944) (14.2881, -2.0787) (14.3436, -2.0624) (14.3991, -2.0455) (14.4546, -2.0281) (14.5101, -2.0101) (14.5655, -1.9917) (14.6209, -1.9726) (14.6763, -1.953) (14.7316, -1.9329) (14.7869, -1.9123) (14.8421, -1.8911) (14.8973, -1.8695) (14.9524, -1.8473) (15.0075, -1.8247) (15.0626, -1.8015) (15.1175, -1.7779) (15.1724, -1.7538) (15.2273, -1.7292) (15.282, -1.7041) (15.3368, -1.6785) (15.3914, -1.6525) (15.446, -1.626) (15.5004, -1.5991) (15.5548, -1.5717) (15.6092, -1.5439) (15.6634, -1.5156) (15.7176, -1.4868) (15.7717, -1.4576) (15.8256, -1.428) (15.8795, -1.3979) (15.9333, -1.3674) (15.9871, -1.3365) (16.0407, -1.3051) (16.0942, -1.2733) (16.1476, -1.2411) (16.2009, -1.2085) (16.2541, -1.1755) (16.3072, -1.142) (16.3602, -1.1081) (16.413, -1.0738) (16.4658, -1.0391) (16.5184, -1.004) (16.571, -0.9685) (16.6234, -0.9327) (16.6757, -0.8964) (16.7174, -0.867) (16.7486, -0.8448) (16.7695, -0.8299) (16.7799, -0.8225) knots 0 0 0 0 0 0 0.01428571 0.02857143 0.04285714 0.05714286 0.07142857 0.08571429 0.1 0.11428571 0.12857143 0.14285714 0.15714286 0.17142857 0.18571429 0.2 0.21428571 0.22857143 0.24285714 0.25714286 0.27142857 0.28571429 0.3 0.31428571 0.32857143 0.34285714 0.35714286 0.37142857 0.38571429 0.4 0.41428571 0.42857143 0.44285714 0.45714286 0.47142857 0.48571429 0.5 0.51428571 0.52857143 0.54285714 0.55714286 0.57142857 0.58571429 0.6 0.61428571 0.62857143 0.64285714 0.65714286 0.67142857 0.68571429 0.7 0.71428571 0.72857143 0.74285714 0.75714286 0.77142857 0.78571429 0.8 0.81428571 0.82857143 0.84285714 0.85714286 0.87142857 0.88571429 0.9 0.91428571 0.92857143 0.94285714 0.95714286 0.97142857 0.98571429 1 1 1 1 1 1
  arc A22 (16.7799, -0.8225) -> (16.7799, 0.8225) centre (0, 0) ccw
  spline S11 degree 5 poles (16.7799, 0.8225) (16.7695, 0.8299) (16.7486, 0.8448) (16.7174, 0.867) (16.6757, 0.8964) (16.6234, 0.9327) (16.571, 0.9685) (16.5184, 1.004) (16.4658, 1.0391) (16.413, 1.0738) (16.3602, 1.1081) (16.3072, 1.142) (16.2541, 1.1755) (16.2009, 1.2085) (16.1476, 1.2411) (16.0942, 1.2733) (16.0407, 1.3051) (15.9871, 1.3365) (15.9333, 1.3674) (15.8795, 1.3979) (15.8256, 1.428) (15.7717, 1.4576) (15.7176, 1.4868) (15.6634, 1.5156) (15.6092, 1.5439) (15.5548, 1.5717) (15.5004, 1.5991) (15.446, 1.626) (15.3914, 1.6525) (15.3368, 1.6785) (15.282, 1.7041) (15.2273, 1.7292) (15.1724, 1.7538) (15.1175, 1.7779) (15.0626, 1.8015) (15.0075, 1.8247) (14.9524, 1.8473) (14.8973, 1.8695) (14.8421, 1.8911) (14.7869, 1.9123) (14.7316, 1.9329) (14.6763, 1.953) (14.6209, 1.9726) (14.5655, 1.9917) (14.5101, 2.0101) (14.4546, 2.0281) (14.3991, 2.0455) (14.3436, 2.0624) (14.2881, 2.0787) (14.2325, 2.0944) (14.1769, 2.1096) (14.1213, 2.1241) (14.0657, 2.138) (14.0101, 2.1511) (13.9546, 2.1637) (13.899, 2.1756) (13.8434, 2.187) (13.7878, 2.1977) (13.7323, 2.2079) (13.6767, 2.2173) (13.6212, 2.226) (13.5658, 2.2337) (13.5104, 2.2404) (13.4551, 2.246) (13.3998, 2.2507) (13.3446, 2.2548) (13.2894, 2.2583) (13.2343, 2.2613) (13.1793, 2.2636) (13.1245, 2.2647) (13.0698, 2.2637) (13.0264, 2.2606) (12.9939, 2.2566) (12.9724, 2.2533) (12.9616, 2.2514) knots -1 -1 -1 -1 -1 -1 -0.98571429 -0.97142857 -0.95714286 -0.94285714 -0.92857143 -0.91428571 -0.9 -0.88571429 -0.87142857 -0.85714286 -0.84285714 -0.82857143 -0.81428571 -0.8 -0.78571429 -0.77142857 -0.75714286 -0.74285714 -0.72857143 -0.71428571 -0.7 -0.68571429 -0.67142857 -0.65714286 -0.64285714 -0.62857143 -0.61428571 -0.6 -0.58571429 -0.57142857 -0.55714286 -0.54285714 -0.52857143 -0.51428571 -0.5 -0.48571429 -0.47142857 -0.45714286 -0.44285714 -0.42857143 -0.41428571 -0.4 -0.38571429 -0.37142857 -0.35714286 -0.34285714 -0.32857143 -0.31428571 -0.3 -0.28571429 -0.27142857 -0.25714286 -0.24285714 -0.22857143 -0.21428571 -0.2 -0.18571429 -0.17142857 -0.15714286 -0.14285714 -0.12857143 -0.11428571 -0.1 -0.08571429 -0.07142857 -0.05714286 -0.04285714 -0.02857143 -0.01428571 0 0 0 0 0 0
  line L11 (12.9616, 2.2514) -> (11.3747, 1.9769)
  arc A23 (10.2374, 2.7066) -> (11.3747, 1.9769) centre (11.2042, 2.9622) ccw
  arc A24 (10.2374, 2.7066) -> (9.8732, 3.8277) centre (0, 0) ccw
  arc A25 (10.3643, 5.0866) -> (9.8732, 3.8277) centre (10.8056, 4.1892) ccw
  line L12 (10.3643, 5.0866) -> (11.8095, 5.7972)
  spline S12 degree 5 poles (11.8095, 5.7972) (11.8193, 5.802) (11.8387, 5.812) (11.8673, 5.8279) (11.9043, 5.8509) (11.9491, 5.8822) (11.9928, 5.9153) (12.036, 5.9495) (12.0788, 5.9844) (12.1213, 6.0196) (12.1636, 6.0553) (12.2055, 6.0916) (12.247, 6.1287) (12.2879, 6.1667) (12.3282, 6.2055) (12.368, 6.2451) (12.4074, 6.2854) (12.4464, 6.3263) (12.485, 6.3677) (12.5233, 6.4095) (12.5613, 6.4518) (12.5989, 6.4946) (12.6361, 6.538) (12.6729, 6.5819) (12.7093, 6.6263) (12.7454, 6.6712) (12.7811, 6.7166) (12.8164, 6.7625) (12.8515, 6.8087) (12.8861, 6.8554) (12.9204, 6.9026) (12.9544, 6.9501) (12.988, 6.9981) (13.0213, 7.0465) (13.0543, 7.0952) (13.0869, 7.1444) (13.1191, 7.194) (13.151, 7.244) (13.1826, 7.2943) (13.2139, 7.345) (13.2448, 7.3961) (13.2753, 7.4475) (13.3056, 7.4993) (13.3355, 7.5514) (13.3651, 7.6039) (13.3943, 7.6568) (13.4232, 7.7099) (13.4518, 7.7634) (13.48, 7.8172) (13.508, 7.8714) (13.5355, 7.9258) (13.5628, 7.9806) (13.5897, 8.0357) (13.6163, 8.0911) (13.6426, 8.1468) (13.6685, 8.2028) (13.6941, 8.2591) (13.7194, 8.3157) (13.7443, 8.3726) (13.7689, 8.4298) (13.7932, 8.4872) (13.8171, 8.5449) (13.8407, 8.603) (13.864, 8.6612) (13.887, 8.7198) (13.9096, 8.7786) (13.9319, 8.8377) (13.9539, 8.897) (13.9755, 8.9566) (13.9968, 9.0164) (14.0178, 9.0765) (14.0343, 9.1248) (14.0465, 9.1611) (14.0546, 9.1854) (14.0586, 9.1976) knots 0 0 0 0 0 0 0.01428571 0.02857143 0.04285714 0.05714286 0.07142857 0.08571429 0.1 0.11428571 0.12857143 0.14285714 0.15714286 0.17142857 0.18571429 0.2 0.21428571 0.22857143 0.24285714 0.25714286 0.27142857 0.28571429 0.3 0.31428571 0.32857143 0.34285714 0.35714286 0.37142857 0.38571429 0.4 0.41428571 0.42857143 0.44285714 0.45714286 0.47142857 0.48571429 0.5 0.51428571 0.52857143 0.54285714 0.55714286 0.57142857 0.58571429 0.6 0.61428571 0.62857143 0.64285714 0.65714286 0.67142857 0.68571429 0.7 0.71428571 0.72857143 0.74285714 0.75714286 0.77142857 0.78571429 0.8 0.81428571 0.82857143 0.84285714 0.85714286 0.87142857 0.88571429 0.9 0.91428571 0.92857143 0.94285714 0.95714286 0.97142857 0.98571429 1 1 1 1 1 1
  arc A26 (14.0586, 9.1976) -> (13.0918, 10.5283) centre (0, 0) ccw
  spline S13 degree 5 poles (13.0918, 10.5283) (13.079, 10.5283) (13.0534, 10.5281) (13.0151, 10.5277) (12.964, 10.5269) (12.9004, 10.5255) (12.8369, 10.5237) (12.7735, 10.5216) (12.7103, 10.519) (12.6472, 10.5161) (12.5843, 10.5128) (12.5215, 10.509) (12.4589, 10.5049) (12.3965, 10.5003) (12.3341, 10.4954) (12.272, 10.4901) (12.21, 10.4843) (12.1482, 10.4782) (12.0866, 10.4716) (12.0251, 10.4647) (11.9639, 10.4573) (11.9028, 10.4496) (11.8419, 10.4414) (11.7812, 10.4328) (11.7206, 10.4238) (11.6603, 10.4144) (11.6002, 10.4046) (11.5403, 10.3944) (11.4806, 10.3837) (11.4211, 10.3727) (11.3618, 10.3612) (11.3027, 10.3493) (11.2439, 10.337) (11.1853, 10.3242) (11.127, 10.311) (11.0688, 10.2974) (11.011, 10.2833) (10.9533, 10.2689) (10.8959, 10.2539) (10.8388, 10.2386) (10.782, 10.2228) (10.7254, 10.2065) (10.6691, 10.1898) (10.6131, 10.1727) (10.5574, 10.1551) (10.5019, 10.137) (10.4468, 10.1184) (10.392, 10.0994) (10.3375, 10.08) (10.2833, 10.0601) (10.2294, 10.0397) (10.1759, 10.0187) (10.1228, 9.9973) (10.07, 9.9753) (10.0177, 9.9528) (9.9657, 9.9297) (9.9141, 9.9062) (9.8628, 9.8823) (9.8119, 9.8578) (9.7614, 9.8328) (9.7114, 9.8072) (9.662, 9.7809) (9.6133, 9.7537) (9.5652, 9.7257) (9.5177, 9.6971) (9.4707, 9.6679) (9.424, 9.6383) (9.3777, 9.6084) (9.3318, 9.5779) (9.2868, 9.5465) (9.2432, 9.5136) (9.2098, 9.4855) (9.1859, 9.4633) (9.1704, 9.4479) (9.1628, 9.4401) knots -1 -1 -1 -1 -1 -1 -0.98571429 -0.97142857 -0.95714286 -0.94285714 -0.92857143 -0.91428571 -0.9 -0.88571429 -0.87142857 -0.85714286 -0.84285714 -0.82857143 -0.81428571 -0.8 -0.78571429 -0.77142857 -0.75714286 -0.74285714 -0.72857143 -0.71428571 -0.7 -0.68571429 -0.67142857 -0.65714286 -0.64285714 -0.62857143 -0.61428571 -0.6 -0.58571429 -0.57142857 -0.55714286 -0.54285714 -0.52857143 -0.51428571 -0.5 -0.48571429 -0.47142857 -0.45714286 -0.44285714 -0.42857143 -0.41428571 -0.4 -0.38571429 -0.37142857 -0.35714286 -0.34285714 -0.32857143 -0.31428571 -0.3 -0.28571429 -0.27142857 -0.25714286 -0.24285714 -0.22857143 -0.21428571 -0.2 -0.18571429 -0.17142857 -0.15714286 -0.14285714 -0.12857143 -0.11428571 -0.1 -0.08571429 -0.07142857 -0.05714286 -0.04285714 -0.02857143 -0.01428571 0 0 0 0 0 0
  line L13 (9.1628, 9.4401) -> (8.0404, 8.2852)
  arc A27 (6.6914, 8.2071) -> (8.0404, 8.2852) centre (7.3233, 8.9822) ccw
  arc A28 (6.6914, 8.2071) -> (5.7377, 8.9) centre (0, 0) ccw
  arc A29 (5.3951, 10.2071) -> (5.7377, 8.9) centre (6.2795, 9.7405) ccw
  line L14 (5.3951, 10.2071) -> (6.1466, 11.6315)
  spline S14 degree 5 poles (6.1466, 11.6315) (6.1517, 11.6412) (6.1615, 11.6606) (6.1753, 11.6903) (6.1917, 11.7307) (6.2095, 11.7823) (6.2255, 11.8348) (6.2402, 11.8878) (6.2544, 11.9412) (6.2681, 11.9947) (6.2813, 12.0484) (6.2939, 12.1025) (6.3057, 12.1568) (6.3164, 12.2116) (6.3262, 12.2667) (6.3352, 12.3221) (6.3433, 12.3779) (6.3508, 12.4339) (6.3578, 12.49) (6.3642, 12.5464) (6.37, 12.603) (6.3752, 12.6597) (6.3799, 12.7167) (6.3839, 12.7738) (6.3872, 12.8312) (6.39, 12.8887) (6.3922, 12.9464) (6.3938, 13.0043) (6.395, 13.0623) (6.3956, 13.1204) (6.3956, 13.1787) (6.3952, 13.2372) (6.3942, 13.2957) (6.3927, 13.3545) (6.3906, 13.4133) (6.3881, 13.4722) (6.385, 13.5313) (6.3815, 13.5905) (6.3775, 13.6498) (6.3729, 13.7092) (6.3679, 13.7686) (6.3624, 13.8282) (6.3565, 13.8879) (6.35, 13.9477) (6.3431, 14.0075) (6.3357, 14.0674) (6.3278, 14.1274) (6.3195, 14.1875) (6.3107, 14.2476) (6.3015, 14.3079) (6.2918, 14.3681) (6.2816, 14.4285) (6.271, 14.4889) (6.26, 14.5493) (6.2485, 14.6098) (6.2365, 14.6704) (6.2242, 14.731) (6.2113, 14.7916) (6.1981, 14.8523) (6.1844, 14.913) (6.1703, 14.9737) (6.1557, 15.0345) (6.1407, 15.0953) (6.1253, 15.1562) (6.1095, 15.217) (6.0932, 15.2779) (6.0765, 15.3388) (6.0594, 15.3997) (6.0419, 15.4606) (6.0239, 15.5216) (6.0055, 15.5825) (5.9905, 15.6313) (5.9791, 15.6679) (5.9714, 15.6922) (5.9675, 15.7044) knots 0 0 0 0 0 0 0.01428571 0.02857143 0.04285714 0.05714286 0.07142857 0.08571429 0.1 0.11428571 0.12857143 0.14285714 0.15714286 0.17142857 0.18571429 0.2 0.21428571 0.22857143 0.24285714 0.25714286 0.27142857 0.28571429 0.3 0.31428571 0.32857143 0.34285714 0.35714286 0.37142857 0.38571429 0.4 0.41428571 0.42857143 0.44285714 0.45714286 0.47142857 0.48571429 0.5 0.51428571 0.52857143 0.54285714 0.55714286 0.57142857 0.58571429 0.6 0.61428571 0.62857143 0.64285714 0.65714286 0.67142857 0.68571429 0.7 0.71428571 0.72857143 0.74285714 0.75714286 0.77142857 0.78571429 0.8 0.81428571 0.82857143 0.84285714 0.85714286 0.87142857 0.88571429 0.9 0.91428571 0.92857143 0.94285714 0.95714286 0.97142857 0.98571429 1 1 1 1 1 1
  arc A30 (5.9675, 15.7044) -> (4.403, 16.2127) centre (0, 0) ccw